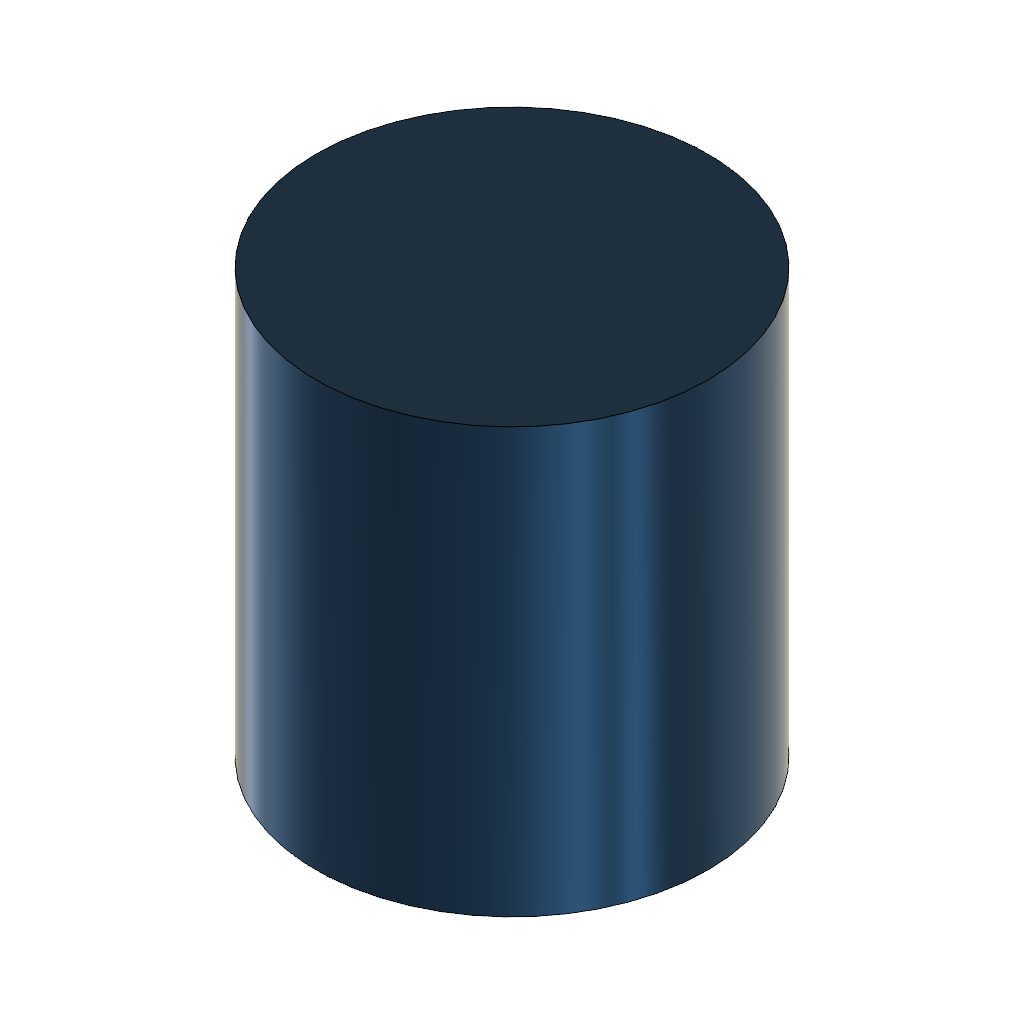
vendor_CylinderIdsReemittedSaved (Autodesk Fusion 360 design; units mm, degrees)
Autodesk Fusion 360 part; units mm, degrees
sketch "Public Profile" plane through (0, 0, 0) normal (0, 0, 1) x (1, 0, 0)
  circle A0 centre (0, 0) radius 12
extrude "Public Extrusion" add sketch "Public Profile" along normal blind 26
equation "publicHeight = 26 mm"
equation "d2 = publicHeight"
